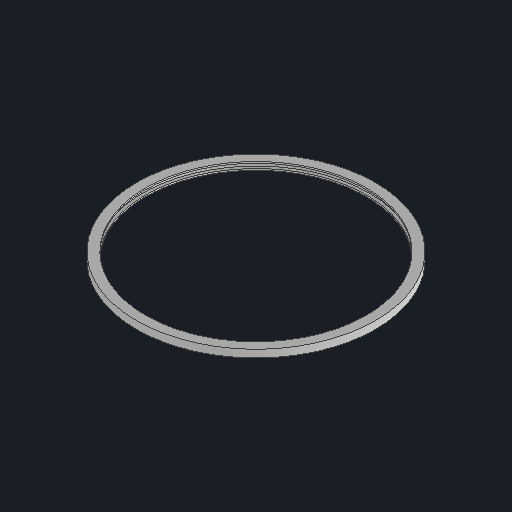
# Autodesk Inventor part: SealOut
Saved by Autodesk Inventor 2027.2 (Build 312334000, 334)
## iProperties
Created: 2026-11-16
Part Number: SealOut
Material: Generic
Document SubType Name: Modeling
Designer: Gasteng5
Density: 1 g/cm^3
Appearance: Default
Author: Gasteng5
Comments: Sillicone-Si-beige
Autodesk Inventor part; units mm, degrees
ref_plane "YZ Plane" through (0, 0, 0) normal (1, 0, 0) x (0, 1, 0)
ref_plane "XZ Plane" through (0, 0, 0) normal (0, 1, 0) x (-1, 0, 0)
ref_plane "XY Plane" through (0, 0, 0) normal (0, 0, 1) x (1, 0, 0)
sketch "Sketch1" plane through (0, 0, 0) normal (1, 0, 0) x (0, 1, 0)
  line L0 (0, 0) -> (-111.5, 0)
  line L1 (-111.5, -2.25) -> (-111.5, 2.25)
  line L2 (-111.5, 2.25) -> (-108.5, 2.25)
  line L3 (-108.5, 2.25) -> (-108.5, 3.75)
  line L4 (-108.5, 3.75) -> (-117.5, 3.75)
  line L5 (-117.5, 3.75) -> (-117.5, 0)
  line L6 (-111.5, 0) -> (-46.2012, 0)
  line L7 (-111.5, -2.25) -> (-108.5, -2.25)
  line L8 (-108.5, -2.25) -> (-108.5, -3.75)
  line L9 (-108.5, -3.75) -> (-117.5, -3.75)
  line L10 (-117.5, -3.75) -> (-117.5, 0)
  line L11 (0, -5.25) -> (0, 5.25) projected
  dimension "d0" = 111.5
  dimension "d1" = 4.5
  dimension "d3" = 1.5
  dimension "d4" = 3
  dimension "d8" = 117.5
  constraints: 22 end point, 4 perpendicular, 3 horizontal, 3 symmetric about line, 1 midpoint, 1 point on line, 1 vertical
  measures "d0" distance of L0.start L0.end
  measures "d1" distance of L1.start L1.end
  measures "d3" distance of L2.end L3.end
  measures "d4" distance of L1.end L2.end
  measures "d8" distance from line of L0.start L5
revolve "Revolution1" add sketch "Sketch1" angle 360 about axis through (0, 0, -10) along (0, 0, 1)
equation "\"d0\" = 0.5 * BinnenDiaMeter"
equation "\"d8\" = 0.5 * BuitenDiaMeter"
equation "\"BinnenDiaMeter\" = 223"
equation "\"BuitenDiaMeter\" = 235"
body "Solid1"
